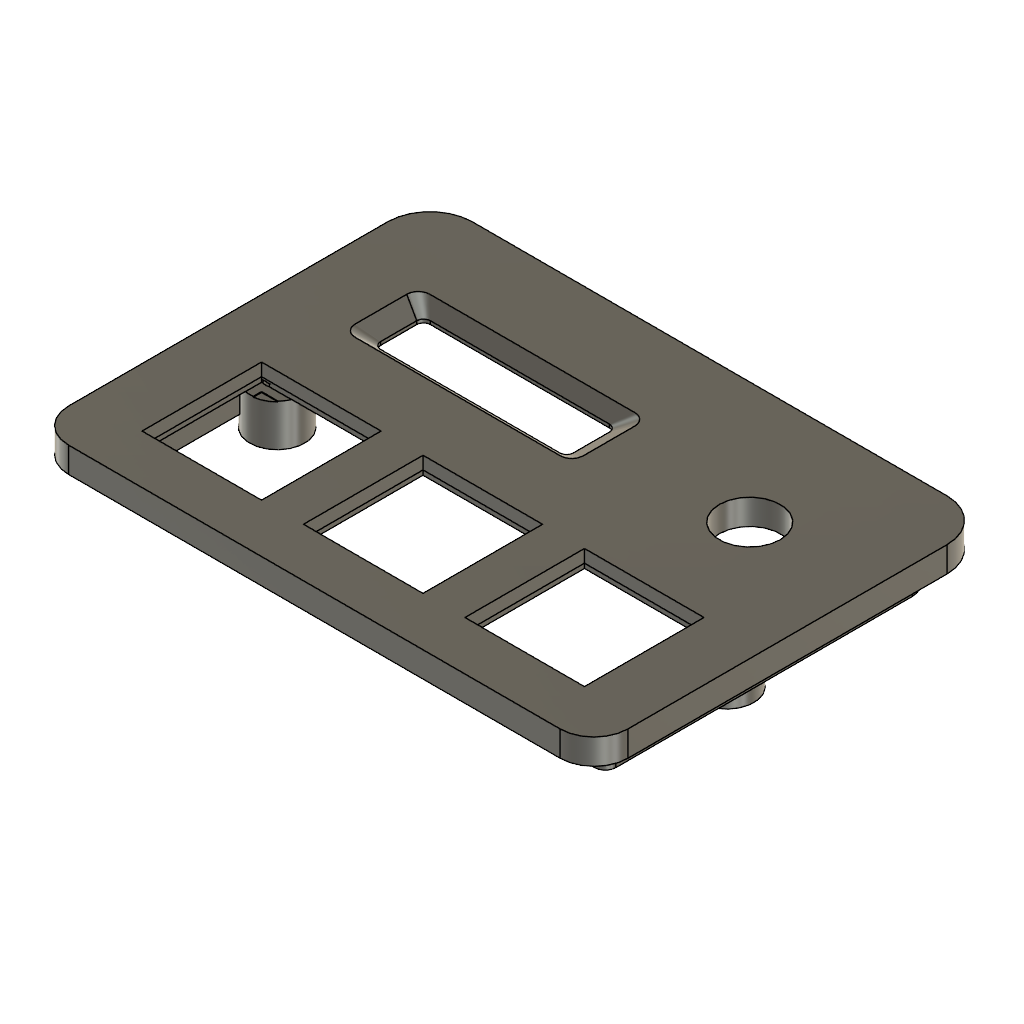
FrontPlate_Fit (Autodesk Fusion 360 design; units mm, degrees)
part number: 2026-10-25-12-48-00-965
Autodesk Fusion 360 part; units mm, degrees
sketch "01 Lid outline - Y compensated" plane through (0, 0, 0) normal (0, 0, 1) x (1, 0, 0)
  arc A0 (-33, -19.3251) -> (-29, -23.3251) centre (-29, -19.3251) ccw
  arc A1 (29, -23.3251) -> (33, -19.3251) centre (29, -19.3251) ccw
  arc A2 (33, 18.3251) -> (28, 23.3251) centre (28, 18.3251) ccw
  arc A3 (-28, 23.3251) -> (-33, 18.3251) centre (-28, 18.3251) ccw
  line L0 (-29, -23.3251) -> (29, -23.3251)
  line L1 (33, -19.3251) -> (33, 18.3251)
  line L2 (28, 23.3251) -> (-28, 23.3251)
  line L3 (-33, 18.3251) -> (-33, -19.3251)
  dimension "d64" = 29
  dimension "d65" = 19.3251
  dimension "d66" = 4
  dimension "d67" = 29
  dimension "d68" = 19.3251
  dimension "d69" = 4
  dimension "d70" = 28
  dimension "d71" = 18.3251
  dimension "d72" = 5
  dimension "d73" = 28
  dimension "d74" = 18.3251
  dimension "d75" = 5
  constraint horizontal A0.centre A0.start
  constraint vertical A0.centre A0.end
  constraint vertical A1.centre A1.start
  constraint horizontal A1.centre A1.end
  constraint horizontal A2.centre A2.start
  constraint vertical A2.centre A2.end
  constraint vertical A3.centre A3.start
  constraint horizontal A3.centre A3.end
  measures "d64" horizontal distance of origin A0.centre
  measures "d65" vertical distance of origin A0.centre
  measures "d66" radius of A0
  measures "d67" horizontal distance of origin A1.centre
  measures "d68" vertical distance of origin A1.centre
  measures "d69" radius of A1
  measures "d70" horizontal distance of origin A2.centre
  measures "d71" vertical distance of origin A2.centre
  measures "d72" radius of A2
  measures "d73" horizontal distance of origin A3.centre
  measures "d74" vertical distance of origin A3.centre
  measures "d75" radius of A3
extrude "01 Lid face 3 mm" add sketch "01 Lid outline - Y compensated" along normal blind 3
ref_plane "WorkPlane1" through (0, 0, -3) normal (0, 0, 1) x (1, 0, 0)
sketch "02 Locating skirt ring" plane through (0, 0, -3) normal (0, 0, 1) x (1, 0, 0)
  arc A0 (-30.25, -18) -> (-29, -19.25) centre (-29, -18) ccw
  arc A1 (29, -19.25) -> (30.25, -18) centre (29, -18) ccw
  arc A2 (30.25, 17) -> (28, 19.25) centre (28, 17) ccw
  arc A3 (-28, 19.25) -> (-30.25, 17) centre (-28, 17) ccw
  line L0 (-29, -19.25) -> (29, -19.25)
  line L1 (30.25, -18) -> (30.25, 17)
  line L2 (28, 19.25) -> (-28, 19.25)
  line L3 (-30.25, 17) -> (-30.25, -18)
  arc A4 (-28.05, -16.25) -> (-27.25, -17.05) centre (-27.25, -16.25) ccw
  arc A5 (27.25, -17.05) -> (28.05, -16.25) centre (27.25, -16.25) ccw
  arc A6 (28.05, 16.25) -> (27.25, 17.05) centre (27.25, 16.25) ccw
  arc A7 (-27.25, 17.05) -> (-28.05, 16.25) centre (-27.25, 16.25) ccw
  line L4 (-27.25, -17.05) -> (27.25, -17.05)
  line L5 (28.05, -16.25) -> (28.05, 16.25)
  line L6 (27.25, 17.05) -> (-27.25, 17.05)
  line L7 (-28.05, 16.25) -> (-28.05, -16.25)
  dimension "d80" = 29
  dimension "d81" = 18
  dimension "d82" = 1.25
  dimension "d83" = 29
  dimension "d84" = 18
  dimension "d85" = 1.25
  dimension "d86" = 28
  dimension "d87" = 17
  dimension "d88" = 2.25
  dimension "d89" = 28
  dimension "d90" = 17
  dimension "d91" = 2.25
  dimension "d92" = 27.25
  dimension "d93" = 16.25
  dimension "d94" = 0.8
  dimension "d95" = 27.25
  dimension "d96" = 16.25
  dimension "d97" = 0.8
  dimension "d98" = 27.25
  dimension "d99" = 16.25
  dimension "d100" = 0.8
  dimension "d101" = 27.25
  dimension "d102" = 16.25
  dimension "d103" = 0.8
  constraint horizontal A0.centre A0.start
  constraint vertical A0.centre A0.end
  constraint vertical A1.centre A1.start
  constraint horizontal A1.centre A1.end
  constraint horizontal A2.centre A2.start
  constraint vertical A2.centre A2.end
  constraint vertical A3.centre A3.start
  constraint horizontal A3.centre A3.end
  constraint horizontal A4.centre A4.start
  constraint vertical A4.centre A4.end
  constraint vertical A5.centre A5.start
  constraint horizontal A5.centre A5.end
  constraint horizontal A6.centre A6.start
  constraint vertical A6.centre A6.end
  constraint vertical A7.centre A7.start
  constraint horizontal A7.centre A7.end
  measures "d80" horizontal distance of origin A0.centre
  measures "d81" vertical distance of origin A0.centre
  measures "d82" radius of A0
  measures "d83" horizontal distance of origin A1.centre
  measures "d84" vertical distance of origin A1.centre
  measures "d85" radius of A1
  measures "d86" horizontal distance of origin A2.centre
  measures "d87" vertical distance of origin A2.centre
  measures "d88" radius of A2
  measures "d89" horizontal distance of origin A3.centre
  measures "d90" vertical distance of origin A3.centre
  measures "d91" radius of A3
  measures "d92" horizontal distance of origin A4.centre
  measures "d93" vertical distance of origin A4.centre
  measures "d94" radius of A4
  measures "d95" horizontal distance of origin A5.centre
  measures "d96" vertical distance of origin A5.centre
  measures "d97" radius of A5
  measures "d98" horizontal distance of origin A6.centre
  measures "d99" vertical distance of origin A6.centre
  measures "d100" radius of A6
  measures "d101" horizontal distance of origin A7.centre
  measures "d102" vertical distance of origin A7.centre
  measures "d103" radius of A7
extrude "02 Locating skirt" add sketch "02 Locating skirt ring" along normal blind 3.2
sketch "03 Top screw bosses" plane through (0, 0, 0) normal (0, 0, 1) x (1, 0, 0)
  circle A0 centre (-26.5, -1.2) radius 3.25
  circle A1 centre (26.5, -1.2) radius 3.25
  dimension "d106" = 26.5
  dimension "d108" = 6.5
  dimension "d109" = 26.5
  dimension "d110" = 1.2
  dimension "d111" = 6.5
  measures "d106" horizontal distance of origin A0.centre
  measures "d108" diameter of A0
  measures "d109" horizontal distance of origin A1.centre
  measures "d110" vertical distance of origin A1.centre
  measures "d111" diameter of A1
extrude "03 Bosses depth 5 mm" add sketch "03 Top screw bosses" against normal blind 5
ref_plane "WorkPlane2" through (0, 0, -0.1) normal (0, 0, 1) x (1, 0, 0)
sketch "04 OLED pixel window" plane through (0, 0, -0.1) normal (0, 0, 1) x (1, 0, 0)
  arc A0 (-22.37, 6.87) -> (-21.57, 6.07) centre (-21.57, 6.87) ccw
  arc A1 (-0.43, 6.07) -> (0.37, 6.87) centre (-0.43, 6.87) ccw
  arc A2 (0.37, 11.13) -> (-0.43, 11.93) centre (-0.43, 11.13) ccw
  arc A3 (-21.57, 11.93) -> (-22.37, 11.13) centre (-21.57, 11.13) ccw
  line L0 (-21.57, 6.07) -> (-0.43, 6.07)
  line L1 (0.37, 6.87) -> (0.37, 11.13)
  line L2 (-0.43, 11.93) -> (-21.57, 11.93)
  line L3 (-22.37, 11.13) -> (-22.37, 6.87)
  dimension "d116" = 21.57
  dimension "d117" = 6.87
  dimension "d118" = 0.8
  dimension "d119" = 0.43
  dimension "d120" = 6.87
  dimension "d121" = 0.8
  dimension "d122" = 0.43
  dimension "d123" = 11.13
  dimension "d124" = 0.8
  dimension "d125" = 21.57
  dimension "d126" = 11.13
  dimension "d127" = 0.8
  constraint horizontal A0.centre A0.start
  constraint vertical A0.centre A0.end
  constraint vertical A1.centre A1.start
  constraint horizontal A1.centre A1.end
  constraint horizontal A2.centre A2.start
  constraint vertical A2.centre A2.end
  constraint vertical A3.centre A3.start
  constraint horizontal A3.centre A3.end
  measures "d116" horizontal distance of origin A0.centre
  measures "d117" vertical distance of origin A0.centre
  measures "d118" radius of A0
  measures "d119" horizontal distance of origin A1.centre
  measures "d120" vertical distance of origin A1.centre
  measures "d121" radius of A1
  measures "d122" horizontal distance of origin A2.centre
  measures "d123" vertical distance of origin A2.centre
  measures "d124" radius of A2
  measures "d125" horizontal distance of origin A3.centre
  measures "d126" vertical distance of origin A3.centre
  measures "d127" radius of A3
extrude "04 OLED pixel passage" cut sketch "04 OLED pixel window" along normal blind 2.05
ref_plane "WorkPlane3" through (0, 0, 1.8) normal (0, 0, 1) x (1, 0, 0)
sketch "05 Bezel inner profile" plane through (0, 0, 1.8) normal (0, 0, 1) x (1, 0, 0)
  arc A0 (-22.37, 6.87) -> (-21.57, 6.07) centre (-21.57, 6.87) ccw
  arc A1 (-0.43, 6.07) -> (0.37, 6.87) centre (-0.43, 6.87) ccw
  arc A2 (0.37, 11.13) -> (-0.43, 11.93) centre (-0.43, 11.13) ccw
  arc A3 (-21.57, 11.93) -> (-22.37, 11.13) centre (-21.57, 11.13) ccw
  line L0 (-21.57, 6.07) -> (-0.43, 6.07)
  line L1 (0.37, 6.87) -> (0.37, 11.13)
  line L2 (-0.43, 11.93) -> (-21.57, 11.93)
  line L3 (-22.37, 11.13) -> (-22.37, 6.87)
  dimension "d132" = 21.57
  dimension "d133" = 6.87
  dimension "d134" = 0.8
  dimension "d135" = 0.43
  dimension "d136" = 6.87
  dimension "d137" = 0.8
  dimension "d138" = 0.43
  dimension "d139" = 11.13
  dimension "d140" = 0.8
  dimension "d141" = 21.57
  dimension "d142" = 11.13
  dimension "d143" = 0.8
  constraint horizontal A0.centre A0.start
  constraint vertical A0.centre A0.end
  constraint vertical A1.centre A1.start
  constraint horizontal A1.centre A1.end
  constraint horizontal A2.centre A2.start
  constraint vertical A2.centre A2.end
  constraint vertical A3.centre A3.start
  constraint horizontal A3.centre A3.end
  measures "d132" horizontal distance of origin A0.centre
  measures "d133" vertical distance of origin A0.centre
  measures "d134" radius of A0
  measures "d135" horizontal distance of origin A1.centre
  measures "d136" vertical distance of origin A1.centre
  measures "d137" radius of A1
  measures "d138" horizontal distance of origin A2.centre
  measures "d139" vertical distance of origin A2.centre
  measures "d140" radius of A2
  measures "d141" horizontal distance of origin A3.centre
  measures "d142" vertical distance of origin A3.centre
  measures "d143" radius of A3
ref_plane "WorkPlane4" through (0, 0, 3.08) normal (0, 0, 1) x (1, 0, 0)
sketch "06 Bezel outer profile" plane through (0, 0, 3.08) normal (0, 0, 1) x (1, 0, 0)
  arc A0 (-24.6, 5.9) -> (-23.2, 4.5) centre (-23.2, 5.9) ccw
  arc A1 (1.2, 4.5) -> (2.6, 5.9) centre (1.2, 5.9) ccw
  arc A2 (2.6, 12.1) -> (1.2, 13.5) centre (1.2, 12.1) ccw
  arc A3 (-23.2, 13.5) -> (-24.6, 12.1) centre (-23.2, 12.1) ccw
  line L0 (-23.2, 4.5) -> (1.2, 4.5)
  line L1 (2.6, 5.9) -> (2.6, 12.1)
  line L2 (1.2, 13.5) -> (-23.2, 13.5)
  line L3 (-24.6, 12.1) -> (-24.6, 5.9)
  dimension "d146" = 23.2
  dimension "d147" = 5.9
  dimension "d148" = 1.4
  dimension "d149" = 1.2
  dimension "d150" = 5.9
  dimension "d151" = 1.4
  dimension "d152" = 1.2
  dimension "d153" = 12.1
  dimension "d154" = 1.4
  dimension "d155" = 23.2
  dimension "d156" = 12.1
  dimension "d157" = 1.4
  constraint horizontal A0.centre A0.start
  constraint vertical A0.centre A0.end
  constraint vertical A1.centre A1.start
  constraint horizontal A1.centre A1.end
  constraint horizontal A2.centre A2.start
  constraint vertical A2.centre A2.end
  constraint vertical A3.centre A3.start
  constraint horizontal A3.centre A3.end
  measures "d146" horizontal distance of origin A0.centre
  measures "d147" vertical distance of origin A0.centre
  measures "d148" radius of A0
  measures "d149" horizontal distance of origin A1.centre
  measures "d150" vertical distance of origin A1.centre
  measures "d151" radius of A1
  measures "d152" horizontal distance of origin A2.centre
  measures "d153" vertical distance of origin A2.centre
  measures "d154" radius of A2
  measures "d155" horizontal distance of origin A3.centre
  measures "d156" vertical distance of origin A3.centre
  measures "d157" radius of A3
loft "05 Recessed OLED bezel loft" cut profiles "05 Bezel inner profile", "06 Bezel outer profile" section 1 section 2
ref_plane "WorkPlane5" through (0, 0, -3.27) normal (0, 0, 1) x (1, 0, 0)
sketch "07 OLED PCB pocket and skirt clearance" plane through (0, 0, -3.27) normal (0, 0, 1) x (1, 0, 0)
  line L0 (-30.8, 2.2) -> (8.8, 2.2)
  line L1 (8.8, 2.2) -> (8.8, 15.8)
  line L2 (8.8, 15.8) -> (-30.8, 15.8)
  line L3 (-30.8, 15.8) -> (-30.8, 2.2)
  dimension "d160" = 30.8
  dimension "d161" = 2.2
  dimension "d162" = 39.6
  dimension "d163" = 13.6
  measures "d160" horizontal distance of origin L0.start
  measures "d161" vertical distance of origin L0.start
  measures "d162" distance of L0.start L0.end
  measures "d163" distance of L0.end L1.end
extrude "06 OLED PCB insertion channel" cut sketch "07 OLED PCB pocket and skirt clearance" along normal blind 4.67
ref_plane "WorkPlane6" through (0, 0, -0.1) normal (0, 0, 1) x (1, 0, 0)
sketch "08 Three MX switch openings" plane through (0, 0, -0.1) normal (0, 0, 1) x (1, 0, 0)
  line L0 (-26.1, -17.55) -> (-12, -17.55)
  line L1 (-12, -17.55) -> (-12, -3.45)
  line L2 (-12, -3.45) -> (-26.1, -3.45)
  line L3 (-26.1, -3.45) -> (-26.1, -17.55)
  line L4 (-7.05, -17.55) -> (7.05, -17.55)
  line L5 (7.05, -17.55) -> (7.05, -3.45)
  line L6 (7.05, -3.45) -> (-7.05, -3.45)
  line L7 (-7.05, -3.45) -> (-7.05, -17.55)
  line L8 (12, -17.55) -> (26.1, -17.55)
  line L9 (26.1, -17.55) -> (26.1, -3.45)
  line L10 (26.1, -3.45) -> (12, -3.45)
  line L11 (12, -3.45) -> (12, -17.55)
  dimension "d168" = 26.1
  dimension "d169" = 17.55
  dimension "d170" = 14.1
  dimension "d171" = 14.1
  dimension "d172" = 7.05
  dimension "d173" = 17.55
  dimension "d174" = 14.1
  dimension "d175" = 14.1
  dimension "d176" = 12
  dimension "d177" = 17.55
  dimension "d178" = 14.1
  dimension "d179" = 14.1
  measures "d168" horizontal distance of origin L0.start
  measures "d169" vertical distance of origin L0.start
  measures "d170" distance of L0.start L0.end
  measures "d171" distance of L0.end L1.end
  measures "d172" horizontal distance of origin L4.start
  measures "d173" vertical distance of origin L4.start
  measures "d174" distance of L4.start L4.end
  measures "d175" distance of L4.end L5.end
  measures "d176" horizontal distance of origin L8.start
  measures "d177" vertical distance of origin L8.start
  measures "d178" distance of L8.start L8.end
  measures "d179" distance of L8.end L9.end
extrude "07 Three MX 14.10 openings" cut sketch "08 Three MX switch openings" along normal blind 3.2
ref_plane "WorkPlane7" through (0, 0, -0.02) normal (0, 0, 1) x (1, 0, 0)
sketch "09 MX retention clip reliefs" plane through (0, 0, -0.02) normal (0, 0, 1) x (1, 0, 0)
  line L0 (-27.05, -18.5) -> (-11.05, -18.5)
  line L1 (-11.05, -18.5) -> (-11.05, -2.5)
  line L2 (-11.05, -2.5) -> (-27.05, -2.5)
  line L3 (-27.05, -2.5) -> (-27.05, -18.5)
  line L4 (-8, -18.5) -> (8, -18.5)
  line L5 (8, -18.5) -> (8, -2.5)
  line L6 (8, -2.5) -> (-8, -2.5)
  line L7 (-8, -2.5) -> (-8, -18.5)
  line L8 (11.05, -18.5) -> (27.05, -18.5)
  line L9 (27.05, -18.5) -> (27.05, -2.5)
  line L10 (27.05, -2.5) -> (11.05, -2.5)
  line L11 (11.05, -2.5) -> (11.05, -18.5)
  dimension "d184" = 27.05
  dimension "d185" = 18.5
  dimension "d186" = 16
  dimension "d187" = 16
  dimension "d188" = 8
  dimension "d189" = 18.5
  dimension "d190" = 16
  dimension "d191" = 16
  dimension "d192" = 11.05
  dimension "d193" = 18.5
  dimension "d194" = 16
  dimension "d195" = 16
  measures "d184" horizontal distance of origin L0.start
  measures "d185" vertical distance of origin L0.start
  measures "d186" distance of L0.start L0.end
  measures "d187" distance of L0.end L1.end
  measures "d188" horizontal distance of origin L4.start
  measures "d189" vertical distance of origin L4.start
  measures "d190" distance of L4.start L4.end
  measures "d191" distance of L4.end L5.end
  measures "d192" horizontal distance of origin L8.start
  measures "d193" vertical distance of origin L8.start
  measures "d194" distance of L8.start L8.end
  measures "d195" distance of L8.end L9.end
extrude "08 MX relief - 1.5 mm plate remains" cut sketch "09 MX retention clip reliefs" along normal blind 1.52
ref_plane "WorkPlane8" through (0, 0, -0.1) normal (0, 0, 1) x (1, 0, 0)
sketch "10 Encoder bushing" plane through (0, 0, -0.1) normal (0, 0, 1) x (1, 0, 0)
  circle A0 centre (19.05, 9) radius 3.6
  dimension "d200" = 19.05
  dimension "d201" = 9
  dimension "d202" = 7.2
  measures "d200" horizontal distance of origin A0.centre
  measures "d201" vertical distance of origin A0.centre
  measures "d202" diameter of A0
extrude "09 Encoder diameter 7.2" cut sketch "10 Encoder bushing" along normal blind 3.2
ref_plane "WorkPlane9" through (0, 0, -5.2) normal (0, 0, 1) x (1, 0, 0)
sketch "11 M3 pilot holes" plane through (0, 0, -5.2) normal (0, 0, 1) x (1, 0, 0)
  circle A0 centre (-26.5, -1.2) radius 1.35
  circle A1 centre (26.5, -1.2) radius 1.35
  dimension "d207" = 26.5
  dimension "d209" = 2.7
  dimension "d210" = 26.5
  dimension "d211" = 1.2
  dimension "d212" = 2.7
  measures "d207" horizontal distance of origin A0.centre
  measures "d209" diameter of A0
  measures "d210" horizontal distance of origin A1.centre
  measures "d211" vertical distance of origin A1.centre
  measures "d212" diameter of A1
extrude "10 Blind M3 pilots diameter 2.7" cut sketch "11 M3 pilot holes" along normal blind 5.5
equation "case_w = 66 mm" comment "OpenSCAD V6.15 source"
equation "case_d = 44 mm" comment "OpenSCAD V6.15 source"
equation "bottom_h = 17 mm" comment "OpenSCAD V6.15 source"
equation "top_t = 3 mm" comment "OpenSCAD V6.15 source"
equation "wall = 2.2 mm" comment "OpenSCAD V6.15 source"
equation "front_corner_r = 4.0 mm" comment "OpenSCAD V6.15 source"
equation "rear_corner_r = 5.0 mm" comment "OpenSCAD V6.15 source"
equation "fit = 0.55 mm" comment "OpenSCAD V6.15 source"
equation "oled_pcb_w = 38 mm" comment "OpenSCAD V6.15 source"
equation "oled_pcb_d = 12 mm" comment "OpenSCAD V6.15 source"
equation "oled_pixel_w = 22.74 mm" comment "OpenSCAD V6.15 source"
equation "oled_pixel_d = 5.86 mm" comment "OpenSCAD V6.15 source"
equation "oled_pixel_offset_x = 0 mm" comment "OpenSCAD V6.15 source"
equation "oled_pixel_offset_y = 0 mm" comment "OpenSCAD V6.15 source"
equation "oled_center_x = -11 mm" comment "OpenSCAD V6.15 source"
equation "oled_center_y = 9 mm" comment "OpenSCAD V6.15 source"
equation "oled_recess_depth = 1.4 mm" comment "OpenSCAD V6.15 source"
equation "oled_pcb_clearance = 0.80 mm" comment "OpenSCAD V6.15 source"
equation "oled_skirt_channel_depth = 3.25 mm" comment "OpenSCAD V6.15 source"
equation "oled_bezel_w = 27.2 mm" comment "OpenSCAD V6.15 source"
equation "oled_bezel_d = 9.0 mm" comment "OpenSCAD V6.15 source"
equation "oled_bezel_depth = 1.2 mm" comment "OpenSCAD V6.15 source"
equation "mx_cutout = 14.10 mm" comment "OpenSCAD V6.15 source"
equation "mx_spacing = 19.05 mm" comment "OpenSCAD V6.15 source"
equation "mx_row_y = -10.5 mm" comment "OpenSCAD V6.15 source"
equation "mx_plate_thickness = 1.5 mm" comment "OpenSCAD V6.15 source"
equation "mx_recess_size = 16.0 mm" comment "OpenSCAD V6.15 source"
equation "encoder_x = mx_spacing" comment "OpenSCAD V6.15 source"
equation "encoder_y = 9 mm" comment "OpenSCAD V6.15 source"
equation "encoder_hole = 7.2 mm" comment "OpenSCAD V6.15 source"
equation "screw_clearance = 3.4 mm" comment "OpenSCAD V6.15 source"
equation "screw_head = 6.4 mm" comment "OpenSCAD V6.15 source"
equation "screw_head_depth = 2.0 mm" comment "OpenSCAD V6.15 source"
equation "pilot_hole = 2.7 mm" comment "OpenSCAD V6.15 source"
equation "boss_od = 6.5 mm" comment "OpenSCAD V6.15 source"
equation "boss_inset = 6.5 mm" comment "OpenSCAD V6.15 source"
equation "top_boss_depth = 5.0 mm" comment "OpenSCAD V6.15 source"
equation "boss_mating_clearance = 0.20 mm" comment "OpenSCAD V6.15 source"
equation "usb_w = 10.2 mm" comment "OpenSCAD V6.15 source"
equation "usb_h = 4.4 mm" comment "OpenSCAD V6.15 source"
equation "usb_bezel_w = 12.8 mm" comment "OpenSCAD V6.15 source"
equation "usb_bezel_h = 6.6 mm" comment "OpenSCAD V6.15 source"
equation "usb_bezel_depth = 0.9 mm" comment "OpenSCAD V6.15 source"
equation "usb_center_x = 0 mm" comment "OpenSCAD V6.15 source"
equation "usb_center_z = 5.7 mm" comment "OpenSCAD V6.15 source"
equation "mini_board_w = 18.2 mm" comment "OpenSCAD V6.15 source"
equation "mini_board_l = 23.0 mm" comment "OpenSCAD V6.15 source"
equation "mini_board_t = 1.6 mm" comment "OpenSCAD V6.15 source"
equation "mini_board_center_y = 7.4 mm" comment "OpenSCAD V6.15 source"
equation "mini_board_bottom_z = 3.3 mm" comment "OpenSCAD V6.15 source"
equation "mini_board_clearance = 0.35 mm" comment "OpenSCAD V6.15 source"
equation "mini_rail_t = 1.4 mm" comment "OpenSCAD V6.15 source"
equation "mini_lip_w = 1.1 mm" comment "OpenSCAD V6.15 source"
equation "front_wall_h = 7.0 mm" comment "OpenSCAD V6.15 source"
equation "rear_wall_h = 22.5 mm" comment "OpenSCAD V6.15 source"
equation "top_center_h = ( front_wall_h + rear_wall_h ) / 2" comment "OpenSCAD V6.15 source"
equation "tilt_angle = atan(( rear_wall_h - front_wall_h ) / case_d)" comment "OpenSCAD V6.15 source"
equation "lid_d = case_d / cos(tilt_angle)" comment "OpenSCAD V6.15 source"
equation "floor_t = 2 mm" comment "V6.15 construction dimension"
equation "skirt_depth = 3 mm" comment "V6.15 construction dimension"
equation "skirt_overlap = 0.2 mm" comment "V6.15 construction dimension"
equation "screw_y = -1.2 mm" comment "V6.15 construction dimension"
equation "rail_top = mini_board_bottom_z + mini_board_t + mini_board_clearance + 0.7 mm" comment "V6.15 construction dimension"
equation "d64 = -( ( 0 mm ) - ( ( case_w ) / 2 - ( front_corner_r ) ) )"
equation "d65 = -( ( 0 mm ) - ( ( lid_d ) / 2 - ( front_corner_r ) ) )"
equation "d66 = front_corner_r"
equation "d67 = ( 0 mm ) + ( ( case_w ) / 2 - ( front_corner_r ) )"
equation "d69 = front_corner_r"
equation "d70 = ( 0 mm ) + ( ( case_w ) / 2 - ( rear_corner_r ) )"
equation "d71 = ( 0 mm ) + ( ( lid_d ) / 2 - ( rear_corner_r ) )"
equation "d72 = rear_corner_r"
equation "d73 = -( ( 0 mm ) - ( ( case_w ) / 2 - ( rear_corner_r ) ) )"
equation "d74 = ( 0 mm ) + ( ( lid_d ) / 2 - ( rear_corner_r ) )"
equation "d75 = rear_corner_r"
equation "d76 = top_t"
equation "d78 = -skirt_depth"
equation "d80 = -( ( 0 mm ) - ( ( case_w - 2 * wall - 2 * fit ) / 2 - ( front_corner_r - wall - fit ) ) )"
equation "d81 = -( ( 0 mm ) - ( ( case_d - 2 * wall - 2 * fit ) / 2 - ( front_corner_r - wall - fit ) ) )"
equation "d82 = front_corner_r - wall - fit"
equation "d83 = ( 0 mm ) + ( ( case_w - 2 * wall - 2 * fit ) / 2 - ( front_corner_r - wall - fit ) )"
equation "d85 = front_corner_r - wall - fit"
equation "d86 = ( 0 mm ) + ( ( case_w - 2 * wall - 2 * fit ) / 2 - ( rear_corner_r - wall - fit ) )"
equation "d87 = ( 0 mm ) + ( ( case_d - 2 * wall - 2 * fit ) / 2 - ( rear_corner_r - wall - fit ) )"
equation "d88 = rear_corner_r - wall - fit"
equation "d89 = -( ( 0 mm ) - ( ( case_w - 2 * wall - 2 * fit ) / 2 - ( rear_corner_r - wall - fit ) ) )"
equation "d90 = ( 0 mm ) + ( ( case_d - 2 * wall - 2 * fit ) / 2 - ( rear_corner_r - wall - fit ) )"
equation "d91 = rear_corner_r - wall - fit"
equation "d92 = -( ( 0 mm ) - ( ( case_w - 4 * wall - 2 * fit ) / 2 - ( 0.8 mm ) ) )"
equation "d93 = -( ( 0 mm ) - ( ( case_d - 4 * wall - 2 * fit ) / 2 - ( 0.8 mm ) ) )"
equation "d95 = ( 0 mm ) + ( ( case_w - 4 * wall - 2 * fit ) / 2 - ( 0.8 mm ) )"
equation "d96 = -( ( 0 mm ) - ( ( case_d - 4 * wall - 2 * fit ) / 2 - ( 0.8 mm ) ) )"
equation "d98 = ( 0 mm ) + ( ( case_w - 4 * wall - 2 * fit ) / 2 - ( 0.8 mm ) )"
equation "d99 = ( 0 mm ) + ( ( case_d - 4 * wall - 2 * fit ) / 2 - ( 0.8 mm ) )"
equation "d101 = -( ( 0 mm ) - ( ( case_w - 4 * wall - 2 * fit ) / 2 - ( 0.8 mm ) ) )"
equation "d102 = ( 0 mm ) + ( ( case_d - 4 * wall - 2 * fit ) / 2 - ( 0.8 mm ) )"
equation "d104 = skirt_depth + skirt_overlap"
equation "d106 = -( -case_w / 2 + boss_inset )"
equation "d107 = -( screw_y )"
equation "d108 = boss_od"
equation "d109 = case_w / 2 - boss_inset"
equation "d111 = boss_od"
equation "d112 = -( top_boss_depth )"
equation "d116 = -( ( oled_center_x + oled_pixel_offset_x ) - ( ( oled_pixel_w ) / 2 - ( 0.8 mm ) ) )"
equation "d117 = ( oled_center_y + oled_pixel_offset_y ) - ( ( oled_pixel_d ) / 2 - ( 0.8 mm ) )"
equation "d119 = -( ( oled_center_x + oled_pixel_offset_x ) + ( ( oled_pixel_w ) / 2 - ( 0.8 mm ) ) )"
equation "d122 = -( ( oled_center_x + oled_pixel_offset_x ) + ( ( oled_pixel_w ) / 2 - ( 0.8 mm ) ) )"
equation "d123 = ( oled_center_y + oled_pixel_offset_y ) + ( ( oled_pixel_d ) / 2 - ( 0.8 mm ) )"
equation "d126 = ( oled_center_y + oled_pixel_offset_y ) + ( ( oled_pixel_d ) / 2 - ( 0.8 mm ) )"
equation "d128 = top_t - oled_bezel_depth + 0.25 mm"
equation "d130 = top_t - oled_bezel_depth"
equation "d132 = -( ( oled_center_x + oled_pixel_offset_x ) - ( ( oled_pixel_w ) / 2 - ( 0.8 mm ) ) )"
equation "d133 = ( oled_center_y + oled_pixel_offset_y ) - ( ( oled_pixel_d ) / 2 - ( 0.8 mm ) )"
equation "d135 = -( ( oled_center_x + oled_pixel_offset_x ) + ( ( oled_pixel_w ) / 2 - ( 0.8 mm ) ) )"
equation "d138 = -( ( oled_center_x + oled_pixel_offset_x ) + ( ( oled_pixel_w ) / 2 - ( 0.8 mm ) ) )"
equation "d139 = ( oled_center_y + oled_pixel_offset_y ) + ( ( oled_pixel_d ) / 2 - ( 0.8 mm ) )"
equation "d142 = ( oled_center_y + oled_pixel_offset_y ) + ( ( oled_pixel_d ) / 2 - ( 0.8 mm ) )"
equation "d144 = top_t + 0.08 mm"
equation "d146 = -( ( oled_center_x + oled_pixel_offset_x ) - ( ( oled_bezel_w ) / 2 - ( 1.4 mm ) ) )"
equation "d147 = ( oled_center_y + oled_pixel_offset_y ) - ( ( oled_bezel_d ) / 2 - ( 1.4 mm ) )"
equation "d149 = ( oled_center_x + oled_pixel_offset_x ) + ( ( oled_bezel_w ) / 2 - ( 1.4 mm ) )"
equation "d152 = ( oled_center_x + oled_pixel_offset_x ) + ( ( oled_bezel_w ) / 2 - ( 1.4 mm ) )"
equation "d153 = ( oled_center_y + oled_pixel_offset_y ) + ( ( oled_bezel_d ) / 2 - ( 1.4 mm ) )"
equation "d156 = ( oled_center_y + oled_pixel_offset_y ) + ( ( oled_bezel_d ) / 2 - ( 1.4 mm ) )"
equation "d158 = -oled_skirt_channel_depth - 0.02 mm"
equation "d160 = -( ( oled_center_x ) - ( oled_pcb_w + 2 * oled_pcb_clearance ) / 2 )"
equation "d161 = ( oled_center_y ) - ( oled_pcb_d + 2 * oled_pcb_clearance ) / 2"
equation "d162 = oled_pcb_w + 2 * oled_pcb_clearance"
equation "d163 = oled_pcb_d + 2 * oled_pcb_clearance"
equation "d164 = oled_recess_depth + oled_skirt_channel_depth + 0.02 mm"
equation "d168 = -( ( -mx_spacing ) - ( mx_cutout ) / 2 )"
equation "d169 = -( ( mx_row_y ) - ( mx_cutout ) / 2 )"
equation "d170 = mx_cutout"
equation "d171 = mx_cutout"
equation "d172 = -( ( 0 mm ) - ( mx_cutout ) / 2 )"
equation "d174 = mx_cutout"
equation "d175 = mx_cutout"
equation "d176 = ( mx_spacing ) - ( mx_cutout ) / 2"
equation "d178 = mx_cutout"
equation "d179 = mx_cutout"
equation "d180 = top_t + 0.2 mm"
equation "d184 = -( ( -mx_spacing ) - ( mx_recess_size ) / 2 )"
equation "d185 = -( ( mx_row_y ) - ( mx_recess_size ) / 2 )"
equation "d186 = mx_recess_size"
equation "d187 = mx_recess_size"
equation "d188 = -( ( 0 mm ) - ( mx_recess_size ) / 2 )"
equation "d190 = mx_recess_size"
equation "d191 = mx_recess_size"
equation "d192 = ( mx_spacing ) - ( mx_recess_size ) / 2"
equation "d194 = mx_recess_size"
equation "d195 = mx_recess_size"
equation "d196 = top_t - mx_plate_thickness + 0.02 mm"
equation "d200 = encoder_x"
equation "d201 = encoder_y"
equation "d202 = encoder_hole"
equation "d203 = top_t + 0.2 mm"
equation "d205 = -top_boss_depth - 0.2 mm"
equation "d207 = -( -case_w / 2 + boss_inset )"
equation "d208 = -( screw_y )"
equation "d209 = pilot_hole"
equation "d210 = case_w / 2 - boss_inset"
equation "d212 = pilot_hole"
equation "d213 = top_boss_depth + 0.5 mm"
named bodies: "Top V6.15"
